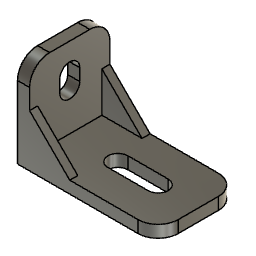
ㄱ자 결합 부품_2024-11-21 (Autodesk Fusion 360 design; units mm, degrees)
Autodesk Fusion 360 part; units mm, degrees
sketch "스케치1" plane through (0, 0, 0) normal (0, 0, 1) x (1, 0, 0)
  line L0 (0, 0) -> (30, 0)
  line L1 (0, 0) -> (0, 20)
  line L2 (0, 20) -> (30, 20)
  line L3 (35, 4.9977) -> (35, 15)
  line L4 (15, 12.5) -> (25, 12.5)
  line L5 (15, 7.5) -> (25, 7.5)
  arc A0 (15, 12.5) -> (15, 7.5) centre (15, 10) ccw
  arc A1 (25, 7.5) -> (25, 12.5) centre (25, 10) ccw
  arc A2 (35, 15) -> (30, 20) centre (30, 15) ccw
  arc A3 (30, 0) -> (35, 5.0023) centre (30, 5) ccw
  constraint horizontal L0
  constraint perpendicular L0 L1
  constraint horizontal L2
  constraint coincident L1 L0.start
  constraint coincident L0 L1.start
  constraint coincident L3.start A3
  constraint coincident L3 A3.end
extrude "돌출1" add sketch "스케치1" along normal blind 3
sketch "스케치2" plane through (0, 0, 3) normal (0, 0, 1) x (-1, 0, 0)
  arc A0 (-15, -12.5) -> (-15, -7.5) centre (-15, -10) ccw
  line L0 (-15, -12.5) -> (-25, -12.5)
  arc A1 (-25, -7.5) -> (-25, -12.5) centre (-25, -10) ccw
  line L1 (-25, -7.5) -> (-15, -7.5)
  line L2 (0, 0) -> (-30, 0)
  arc A2 (-30, 0) -> (-35, -5.0023) centre (-30, -5) ccw
  line L3 (-35, -5.0023) -> (-35, -15)
  arc A3 (-35, -15) -> (-30, -20) centre (-30, -15) ccw
  line L4 (-30, -20) -> (0, -20)
  line L5 (0, -20) -> (0, 0)
  line L6 (0, -20) -> (0, 0)
  line L7 (-3, -20) -> (-3, 0)
  line L8 (0, -20) -> (-3, -20)
  line L9 (0, 0) -> (-3, 0)
  constraint coincident L4.end L5.start
  constraint coincident L2.start L5.end
  constraint perpendicular L7 L8
  constraint perpendicular L7 L9
extrude "돌출2" add sketch "스케치2" along normal blind 20 contours L2 L4 L5 L6 L7 L8 L9
sketch "스케치3" plane through (3, 0, 0) normal (1, 0, 0) x (0, 1, 0)
  line L0 (0, 3) -> (20, 3)
  line L1 (20, 3) -> (20, 23)
  line L2 (20, 23) -> (0, 23)
  line L3 (0, 23) -> (0, 3)
  circle A0 centre (10, 15) radius 2.5
extrude "돌출3" cut sketch "스케치3" against normal blind 3 contours A0
sketch "스케치4" plane through (3, 0, 0) normal (1, 0, 0) x (0, 1, 0)
  circle A0 centre (10, 15) radius 2.5
  line L0 (0, 3) -> (20, 3)
  line L1 (20, 3) -> (20, 23)
  line L2 (20, 23) -> (0, 23)
  line L3 (0, 23) -> (0, 3)
  line L4 (0, 23) -> (0, 18)
  arc A1 (9.9749, 17.4999) -> (10, 18) centre (5, 18) ccw
  arc A2 (5, 23) -> (0, 18) centre (5, 18) ccw
  line L5 (0, 23) -> (5, 23)
  line L6 (15, 23) -> (20, 23)
  arc A3 (10, 18) -> (10.0251, 17.4999) centre (15, 18) ccw
  arc A4 (20, 17.9975) -> (15, 23) centre (15, 18) ccw
  line L7 (20, 23) -> (20, 17.9975)
  constraint coincident L2.end L3.start
  constraint coincident L1.end L2.start
  constraint perpendicular L2 L4
  constraint perpendicular L0 L7
  constraint coincident A2.start A1
  constraint coincident A0 A1.start
  constraint concentric A1 A2
  constraint collinear L5 L6
  constraint coincident A0 A3.end
  constraint concentric A3 A4
  constraint coincident L1 A4.start
extrude "돌출4" cut sketch "스케치4" against normal blind 3 contours L1 L2 L6 A4 L7 | L2 L3 L4 A2 L5
sketch "스케치5" plane through (0, 0, 0) normal (0, -1, 0) x (1, 0, 0)
  line L0 (3, 18) -> (0, 18)
  line L1 (0, 18) -> (0, 0)
  line L2 (0, 0) -> (30, 0)
  line L3 (30, 0) -> (30, 3)
  line L4 (30, 3) -> (3, 3)
  line L5 (3, 3) -> (3, 18)
  line L6 (3, 13) -> (13, 3)
  line L7 (3, 3) -> (13, 3)
  line L8 (3, 3) -> (3, 13)
extrude "돌출5" add sketch "스케치5" against normal blind 2 contours L4 L5 L6 L7 L8
sketch "스케치6" plane through (0, 20, 0) normal (0, 1, 0) x (-1, 0, 0)
  line L0 (0, 18.0015) -> (-3, 18.0015)
  line L1 (-3, 18.0015) -> (-3, 3)
  line L2 (-3, 3) -> (-30, 3)
  line L3 (-30, 3) -> (-30, 0)
  line L4 (-30, 0) -> (0, 0)
  line L5 (0, 0) -> (0, 18.0015)
  line L6 (-13, 3) -> (-3, 3)
  line L7 (-3, 13) -> (-13, 3)
  constraint coincident L2 L6.start
  constraint coincident L1.end L2.start
  constraint coincident L1 L7.start
extrude "돌출6" add sketch "스케치6" against normal blind 2 contours L1 L2 L6 L7
sketch "스케치7" plane through (3, 0, 0) normal (1, 0, 0) x (0, 1, 0)
  line L0 (18, 13) -> (20, 13)
  line L1 (20, 13) -> (20, 18.0015)
  arc A0 (20, 18.0015) -> (15, 23) centre (15, 18) ccw
  line L2 (15, 23) -> (5, 23)
  arc A1 (5, 23) -> (0, 18) centre (5, 18) ccw
  line L3 (0, 18) -> (0, 13)
  line L4 (0, 13) -> (2, 13)
  line L5 (2, 13) -> (2, 3)
  line L6 (2, 3) -> (18, 3)
  line L7 (18, 3) -> (18, 13)
  circle A2 centre (10, 15) radius 2.5
  line L8 (7.5, 16) -> (7.5, 14)
  line L9 (12.5, 16) -> (12.5, 14)
  arc A3 (7.5, 14) -> (12.5, 14) centre (10, 14) ccw
  arc A4 (12.5, 16) -> (7.5, 16) centre (10, 16) ccw
extrude "돌출7" cut sketch "스케치7" against normal blind 3 contours A2 L8 L9 A3 | A2 L8 L9 A4
sketch "스케치8" plane through (3, 0, 0) normal (1, 0, 0) x (0, 1, 0)
  line L0 (12.5, 16) -> (12.5, 14)
  arc A0 (7.5, 14) -> (12.5, 14) centre (10, 14) ccw
  line L1 (7.5, 14) -> (7.5, 16)
  arc A1 (12.5, 16) -> (7.5, 16) centre (10, 16) ccw
  line L2 (18, 13) -> (20, 13)
  line L3 (20, 13) -> (20, 18.0015)
  arc A2 (20, 18.0015) -> (15, 23) centre (15, 18) ccw
  line L4 (15, 23) -> (5, 23)
  arc A3 (5, 23) -> (0, 18) centre (5, 18) ccw
  line L5 (0, 18) -> (0, 13)
  line L6 (0, 13) -> (2, 13)
  line L7 (2, 13) -> (2, 3)
  line L8 (2, 3) -> (18, 3)
  line L9 (18, 3) -> (18, 13)
  line L10 (7.5, 13) -> (7.5, 14)
  line L11 (12.5, 13) -> (12.5, 14)
  arc A4 (7.5, 13) -> (12.5, 13) centre (10, 13) ccw
  constraint coincident A0.start L1.start
  constraint tangent A0 L10
  constraint coincident L0.end A0.end
extrude "돌출8" cut sketch "스케치8" against normal blind 3 contours A0 L10 L11 A4
